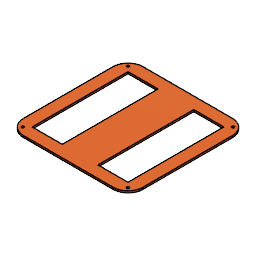
base_inferiore_mENIAC_v3 (Autodesk Fusion 360 design; units mm, degrees)
Autodesk Fusion 360 part; units mm, degrees
sketch "Schizzo1" plane through (0, 0, 0) normal (0, 0, 1) x (1, 0, 0)
  line L0 (-100, 50) -> (100, 50)
  line L1 (100, 50) -> (100, -150)
  line L2 (100, -150) -> (-100, -150)
  line L3 (-100, -150) -> (-100, 50)
  circle A0 centre (-87.9289, 37.9289) radius 2
  circle A1 centre (87.9289, 37.9289) radius 2
  circle A2 centre (87.9289, -137.9289) radius 2
  circle A3 centre (-87.9289, -137.9289) radius 2
  line L4 (-80, 30) -> (-30, 30)
  line L5 (-30, 30) -> (-30, -130)
  line L6 (-30, -130) -> (-80, -130)
  line L7 (-80, -130) -> (-80, 30)
  line L8 (80, 30) -> (30, 30)
  line L9 (30, 30) -> (30, -130)
  line L10 (30, -130) -> (80, -130)
  line L11 (80, -130) -> (80, 30)
  dimension "d1" = 200
  dimension "d2" = 200
  dimension "d6" = 4
  dimension "d12" = 4
  dimension "d15" = 4
  dimension "d16" = 50
  constraint horizontal L0
  constraint vertical L1
  constraint horizontal L2
  constraint vertical L3
  constraint horizontal L4
  constraint vertical L5
  constraint horizontal L6
  constraint vertical L7
  constraint horizontal L8
  constraint vertical L9
  constraint horizontal L10
  constraint vertical L11
  measures "d1" distance of L0.start L0.end
  measures "d2" distance of L0.start L2.end
  measures "d6" diameter of A0
  measures "d12" diameter of A2
  measures "d15" diameter of A3
  measures "d16" distance of L4.start L4.end
extrude "Estrusione1" add sketch "Schizzo1" along normal blind 3
fillet "Raccordo1" radius 25 4 edges at (100, -150, 1.5) (100, 50, 1.5) (-100, 50, 1.5) (-100, -150, 1.5)
